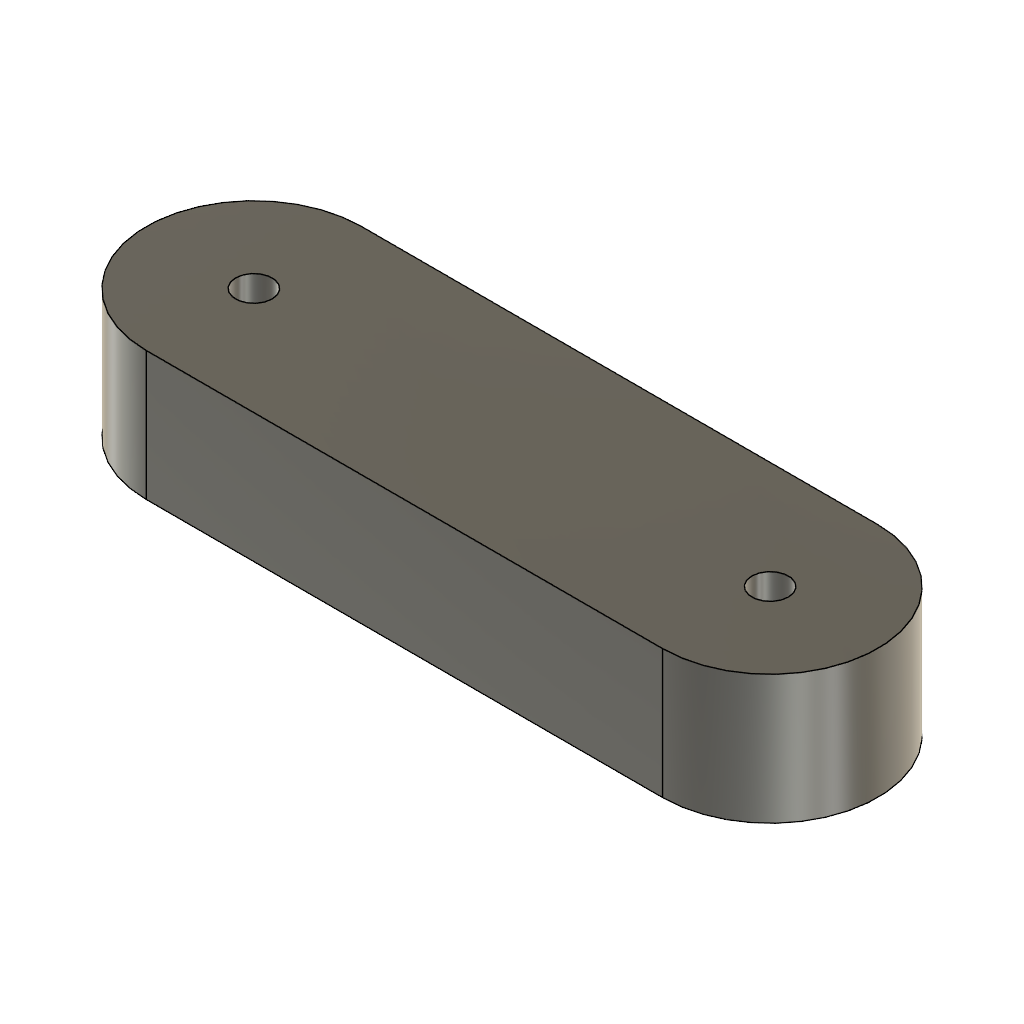
robot rko (Autodesk Fusion 360 archive; units mm, degrees)
design "korbowodV1RKO"
part number: 2026-08-30-19-32-56-895
Autodesk Fusion 360 part; units mm, degrees
sketch "Szkic5" plane through (0, 0, 0) normal (0, 0, 1) x (1, 0, 0)
  line L0 (-60, -25) -> (60, -25)
  arc A0 (60, -25) -> (60, 25) centre (60, 0) ccw
  line L1 (60, 25) -> (-60, 25)
  arc A1 (-60, 25) -> (-60, -25) centre (-60, 0) ccw
  line L2 (-60, 0) -> (60, 0) construction
  circle A2 centre (-60, 0) radius 11.1
  circle A3 centre (60, 0) radius 11.1
  dimension "d15" = 22.2
  dimension "d16" = 22.2
  constraint tangent L0 A0
  constraint tangent A0 L1
  constraint parallel L0 L1
  constraint tangent L1 A1
  constraint tangent L0 A1
  constraint horizontal L2
  constraint midpoint L2 origin
  constraint concentric A1 A2
  constraint concentric A0 A3
  measures "d15" diameter of A2
  measures "d16" diameter of A3
extrude "Wyciągnięcie proste2" add sketch "Szkic5" along normal blind 30
sketch "Szkic6" plane through (0, 0, 30) normal (0, 0, 1) x (-1, 0, 0)
  circle A0 centre (60, 0) radius 11.1
  circle A1 centre (-60, 0) radius 11.1
  arc A2 (60, -25) -> (60, 25) centre (60, 0) ccw
  line L0 (60, 25) -> (-60, 25)
  arc A3 (-60, 25) -> (-60, -25) centre (-60, 0) ccw
  line L1 (-60, -25) -> (60, -25)
  circle A4 centre (-60, 0) radius 4.25
  circle A5 centre (60, 0) radius 4.25
  dimension "d19" = 8.5
  dimension "d20" = 8.5
  constraint concentric A1 A4
  constraint concentric A0 A5
  measures "d19" diameter of A4
  measures "d20" diameter of A5
extrude "Wyciągnięcie proste3" add sketch "Szkic6" against normal blind 11.5 contours A0 | A1

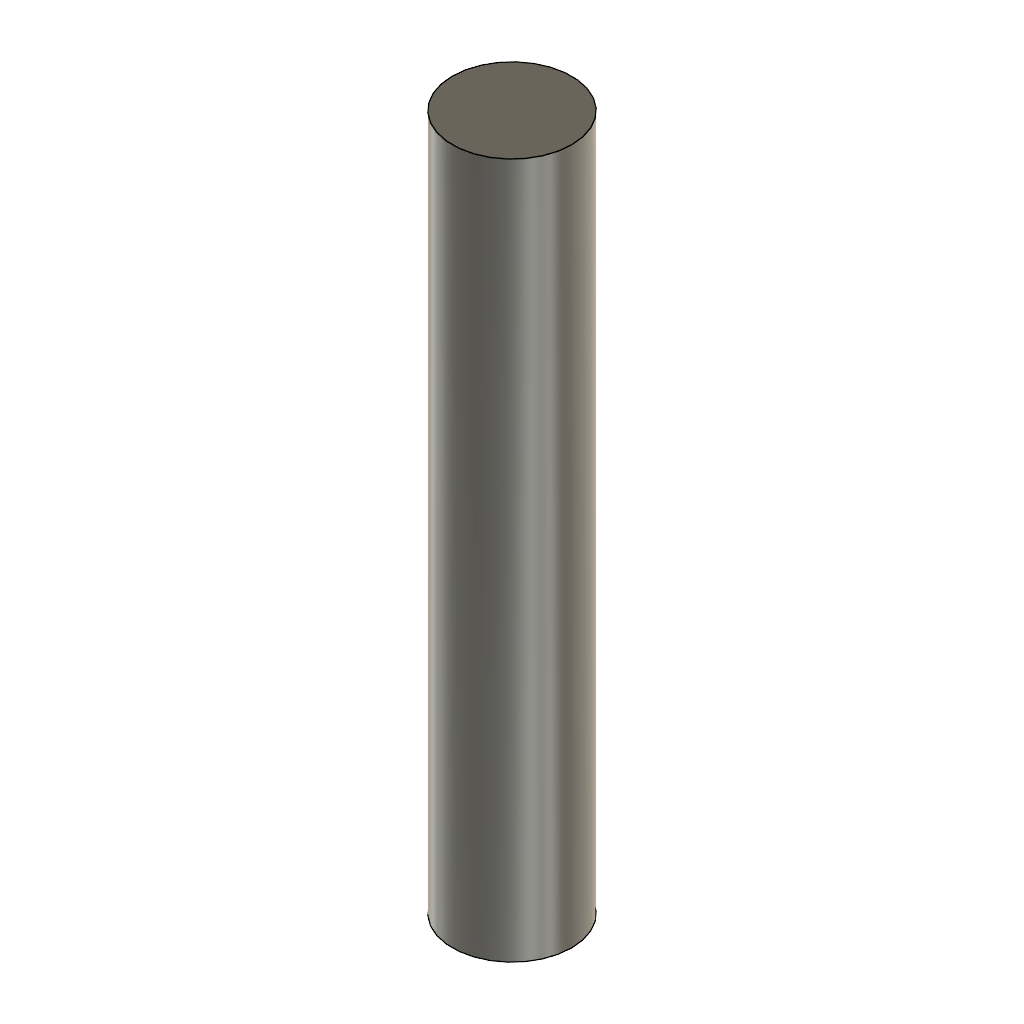
design "wal odbicie"
part number: 2026-10-30-00-36-19-481
Autodesk Fusion 360 part; units mm, degrees
sketch "Szkic1" plane through (0, 0, 0) normal (0, 0, 1) x (1, 0, 0)
  circle A0 centre (0, 0) radius 6
  dimension "d1" = 12
  constraint coincident A0.centre origin
  measures "d1" diameter of A0
extrude "Wyciągnięcie proste1" add sketch "Szkic1" along normal blind 70

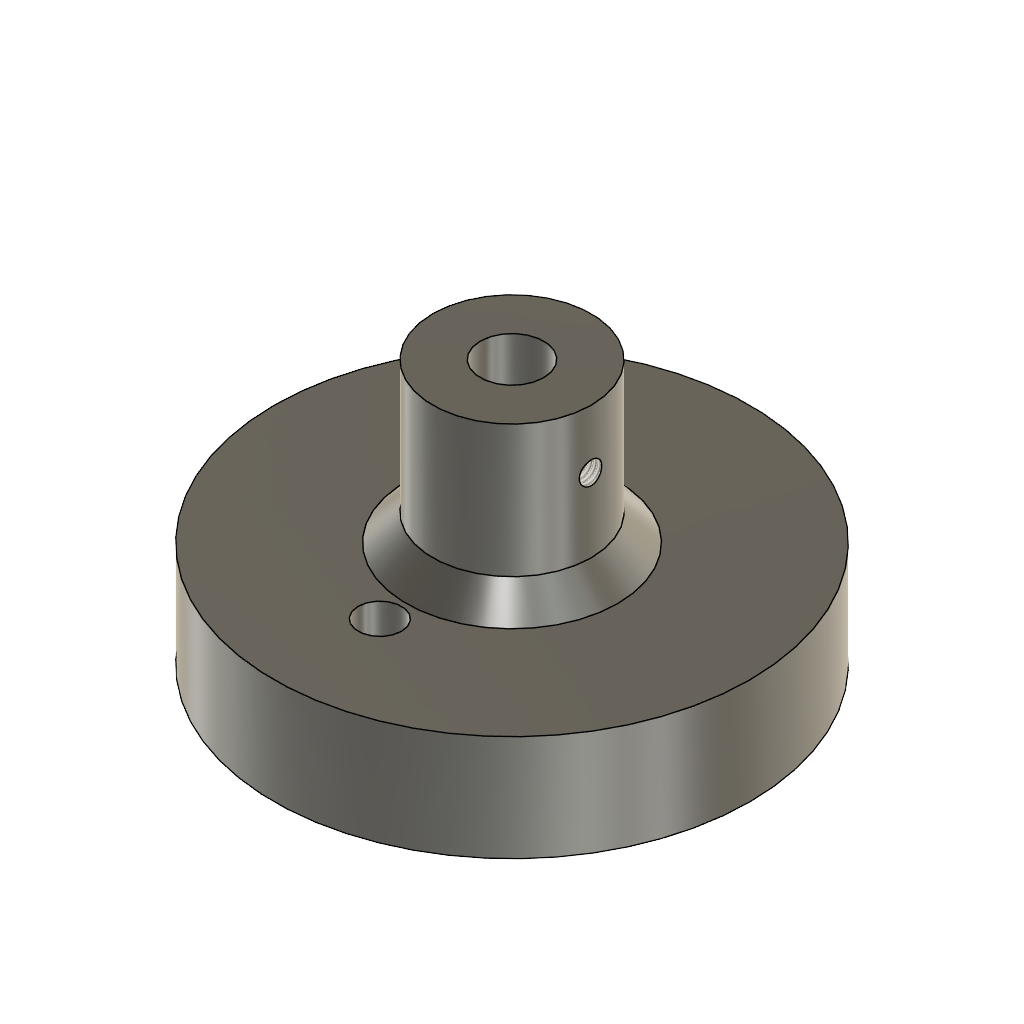
design "korba odbicie"
part number: 2026-10-30-00-32-50-305
Autodesk Fusion 360 part; units mm, degrees
sketch "Szkic1" plane through (0, 0, 0) normal (0, 0, 1) x (1, 0, 0)
  circle A0 centre (0, 0) radius 45
  circle A1 centre (0, -25) radius 4.1
  dimension "d1" = 90
  dimension "d2" = 8.2
  dimension "d3" = 25
  constraint coincident A0.centre origin
  measures "d1" diameter of A0
  measures "d2" diameter of A1
  measures "d3" distance of A0.centre A1.centre
extrude "Wyciągnięcie proste1" add sketch "Szkic1" along normal blind 20
sketch "Szkic2" plane through (0, 0, 20) normal (0, 0, 1) x (-1, 0, 0)
  circle A0 centre (0, 25) radius 4.1
  circle A1 centre (0, 0) radius 45
  circle A2 centre (0, 0) radius 15
  dimension "d6" = 30
  constraint concentric A1 A2
  measures "d6" diameter of A2
extrude "Wyciągnięcie proste2" add sketch "Szkic2" along normal blind 30 contours A2
chamfer "Fazowanie1" distance 5 angle 45 1 edges at (13.9849, -5.4242, 20) tangent chain off
sketch "Szkic3" plane through (0, 0, 50) normal (0, 0, 1) x (-1, 0, 0)
  circle A0 centre (0, 0) radius 15
  circle A1 centre (0, 0) radius 6
  dimension "d10" = 12
  constraint concentric A0 A1
  measures "d10" diameter of A1
extrude "Wyciągnięcie proste3" cut sketch "Szkic3" against normal blind 25 contours A1
hole "Otwór1" at (15, 0, 38.935) direction (-1, 0, 0) diameter 4.234 depth 55 tip angle 180
thread "Gwint1" "ISO Metric profile 5.0 M5x0.8 M5x0.8 6H" major diameter 5.12 minor diameter 4.234 pitch 0.8 angle 60 resizes the face on face at (11.9987, 0.1364, 41.0476) on face at (-11.9965, 0.2005, 41.0425)

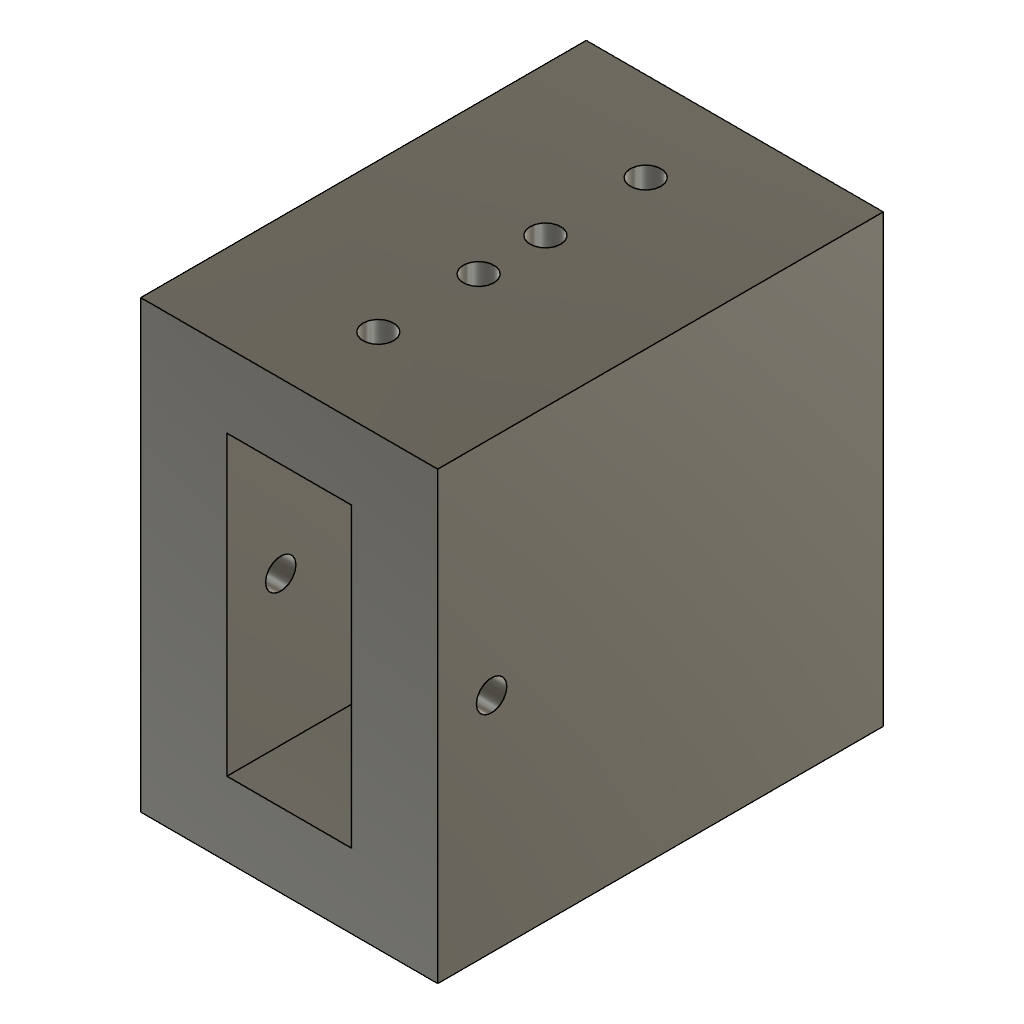
design "suwak-koncepcja osiowego polaczenia"
part number: 2026-10-18-23-51-32-050
Autodesk Fusion 360 part; units mm, degrees
sketch "Szkic1" plane through (0, 0, 0) normal (0, 0, 1) x (1, 0, 0)
  circle A0 centre (0, 9) radius 4.1231
  circle A1 centre (0, 36) radius 4.1231
  circle A2 centre (0, -9) radius 4.1231
  circle A3 centre (0, -36) radius 4.1231
  line L0 (40, -60) -> (-40, -60)
  line L1 (-40, -60) -> (-40, 60)
  line L2 (-40, 60) -> (40, 60)
  line L3 (40, 60) -> (40, -60)
  line L4 (40, -60) -> (-40, 60) construction
  line L5 (-40, -60) -> (40, 60) construction
  dimension "d5" = 0
  dimension "d6" = -27
  dimension "d12" = 0
  dimension "d13" = -72
  dimension "d20" = 0
  dimension "d21" = -45
  dimension "d40" = 120
  dimension "d41" = 80
  constraint horizontal L0
  constraint perpendicular L0 L1
  constraint parallel L0 L2
  constraint parallel L1 L3
  constraint coincident L4 origin
  constraint coincident L5 origin
  measures "d40" distance of L0.end L1.end
  measures "d41" distance of L1.end L2.end
extrude "Wyciągnięcie proste6" add sketch "Szkic1" along normal blind 120
sketch "Szkic5" plane through (0, 60, 0) normal (0, 1, 0) x (-1, 0, 0)
  line L0 (-40, 0) -> (40, 0)
  line L1 (40, 0) -> (40, 120)
  line L2 (40, 120) -> (-40, 120)
  line L3 (-40, 120) -> (-40, 0)
  line L4 (20, 35) -> (-20, 35)
  line L5 (-20, 35) -> (-20, 85)
  line L6 (-20, 85) -> (20, 85)
  line L7 (20, 85) -> (20, 35)
  line L8 (20, 35) -> (-20, 85) construction
  line L9 (-20, 35) -> (20, 85) construction
  line L10 (0, 120) -> (0, 0) construction
  line L11 (-40, 60) -> (40, 60) construction
  point P0 (0, 60)
  dimension "d44" = 40
  dimension "d45" = 50
  constraint horizontal L4
  constraint perpendicular L4 L5
  constraint parallel L4 L6
  constraint parallel L5 L7
  constraint coincident L8 P0
  constraint coincident L9 P0
  constraint coincident L10.end origin
  constraint perpendicular L0 L10
  constraint midpoint L3 L11.start
  constraint midpoint L1 L11.end
  constraint coincident P0 L11
  measures "d44" distance of L5.end L6.end
  measures "d45" distance of L4.end L5.end
extrude "Wyciągnięcie proste7" cut sketch "Szkic5" against normal blind 42 contours L4 L5 L6 L7
sketch "Szkic6" plane through (0, -60, 0) normal (0, -1, 0) x (1, 0, 0)
  line L0 (-40, 0) -> (40, 0)
  line L1 (40, 0) -> (40, 120)
  line L2 (40, 120) -> (-40, 120)
  line L3 (-40, 120) -> (-40, 0)
  line L4 (16.7697, 20) -> (-16.7703, 20)
  line L5 (-16.7703, 20) -> (-16.7703, 100)
  line L6 (-16.7703, 100) -> (16.7697, 100)
  line L7 (16.7697, 100) -> (16.7697, 20)
  line L8 (16.7697, 20) -> (-16.7703, 100) construction
  line L9 (-16.7703, 20) -> (16.7697, 100) construction
  line L10 (0, 120) -> (0, 0) construction
  line L11 (-40, 60) -> (40, 60) construction
  point P0 (-0.0003, 60)
  dimension "d48" = 33.54
  dimension "d49" = 80
  constraint horizontal L4
  constraint perpendicular L4 L5
  constraint parallel L4 L6
  constraint parallel L5 L7
  constraint coincident L8 P0
  constraint coincident L9 P0
  constraint midpoint L2 L10.start
  constraint coincident L10.end origin
  constraint midpoint L3 L11.start
  constraint midpoint L1 L11.end
  constraint coincident P0 L11
  measures "d48" distance of L4.start L4.end
  measures "d49" distance of L4.start L6.end
extrude "Wyciągnięcie proste8" cut sketch "Szkic6" against normal blind 40 contours L4 L5 L6 L7
sketch "Szkic7" plane through (40, 0, 0) normal (1, 0, 0) x (0, 1, 0)
  line L0 (-60, 0) -> (60, 0)
  line L1 (60, 0) -> (60, 120)
  line L2 (60, 120) -> (-60, 120)
  line L3 (-60, 120) -> (-60, 0)
  circle A0 centre (-45.5, 60) radius 4.1
  line L4 (-60, 60) -> (60, 60) construction
  dimension "d55" = 8.2
  dimension "d56" = 14.5
  constraint midpoint L3 L4.start
  constraint midpoint L1 L4.end
  constraint coincident A0.centre L4
  measures "d55" diameter of A0
  measures "d56" distance of L3 A0.centre
extrude "Wyciągnięcie proste9" cut sketch "Szkic7" against normal blind 110 contours A0

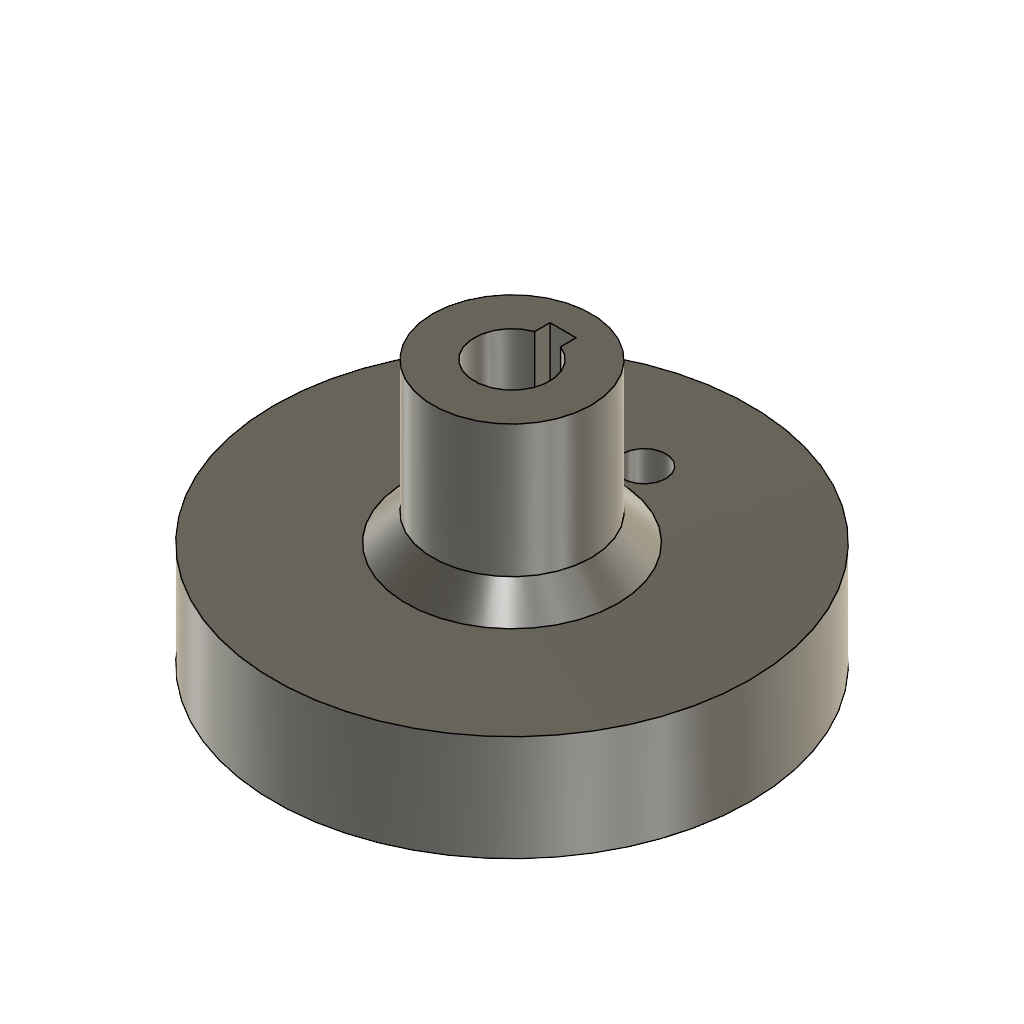
design "KorbaV2RKO"
part number: 2026-10-06-00-30-41-262
Autodesk Fusion 360 part; units mm, degrees
sketch "Szkic1" plane through (0, 0, 0) normal (0, 0, 1) x (1, 0, 0)
  circle A0 centre (0, 0) radius 45
  circle A1 centre (0, 25) radius 3
  dimension "d1" = 90
  dimension "d2" = 6
  dimension "d3" = 25
  constraint coincident A0.centre origin
  measures "d1" diameter of A0
  measures "d2" diameter of A1
  measures "d3" distance of A0.centre A1.centre
extrude "Wyciągnięcie proste1" add sketch "Szkic1" along normal blind 20
sketch "Szkic2" plane through (0, 0, 20) normal (0, 0, 1) x (-1, 0, 0)
  circle A0 centre (0, -25) radius 3
  circle A1 centre (0, 0) radius 45
  circle A2 centre (0, 0) radius 15
  line L0 (-2.5181, -9.6074) -> (2.4162, -9.6074)
  line L1 (2.4162, -9.6074) -> (2.4162, -6.7028)
  line L2 (-2.5181, -6.6652) -> (-2.5181, -9.6074)
  line L3 (-2.5181, -9.6074) -> (2.5519, -4.6093) construction
  line L4 (2.4162, -9.6074) -> (-2.4481, -4.6097) construction
  arc A3 (2.4162, -6.7028) -> (-2.5181, -6.6652) centre (0, 0) ccw
  dimension "d6" = 14.25
  dimension "d7" = 30
  dimension "d10" = 5
  dimension "d11" = 5
  constraint coincident A1.centre A2.centre
  constraint concentric A2 A3
  constraint horizontal L0
  constraint perpendicular L0 L1
  constraint parallel L1 L2
  measures "d6" diameter of A3
  measures "d7" diameter of A2
  measures "d10" distance of L0.end L3.end
  measures "d11" distance of L3.end L4.end
extrude "Wyciągnięcie proste3" add sketch "Szkic2" along normal blind 30 contours A2
chamfer "Fazowanie1" distance 5 angle 45 1 edges at (13.9849, -5.4242, 20) tangent chain off
sketch "Szkic3" plane through (0, 0, 0) normal (0, 0, -1) x (1, 0, 0)
  circle A0 centre (0, -25) radius 3
  circle A1 centre (0, 0) radius 45
  circle A2 centre (0, -25) radius 4.1
  dimension "d16" = 8.2
  constraint concentric A0 A2
  measures "d16" diameter of A2
extrude "Wyciągnięcie proste4" cut sketch "Szkic3" against normal blind 25 contours A0 | A2
extrude "Wyciągnięcie proste2" [suppressed]
